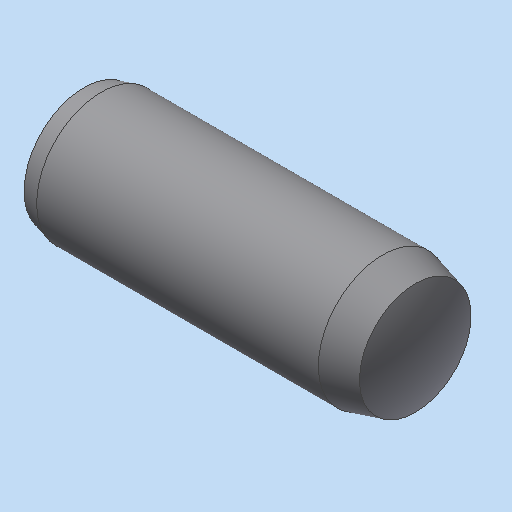
# Autodesk Inventor part: Zylinderstift_DIN_EN_ISO_8735___A6x16
Saved by Autodesk Inventor 2023.3 (Build 273359000, 359)
## iProperties
Shininess: 64.0
Length Units: 11269
Angle Units: 11279
Time Units: 11290
Mass Units: 11283
Length Display Precision: 3
Angle Display Precision: 2
Compacted: True
Part Number: Zylinderstift_DIN_EN_ISO_8735___A6x16
Document SubType Name: Modeling
Created: 2004-04-23
Description: =<RBPARTNOTITLE2>
Vendor: NORM8
Designer: C.Fischer
Manufacturer: Standard
Standards Organization: Custom
Material: xStahl_AnP_Dummymaterial
Mass: 2.68998 g
Surface Area: 4.40403 cm^2
Volume: 0.342673 cm^3
Density: 7.85 g/cm^3
Appearance: RGB(178,178,178)
Density: 0.0
Volumn: 0.0
Area: 0.0
PropertySet Name: Model Information
Control State: 0
Master: False
Checked Out: False
CNS_NB: Zylinderstift DIN EN ISO 8735 - A6x16
CNS_NN: DIN EN ISO 8735-A
CNS_NT: Zylinderstift mit Innengewinde, aus gehaertet Stahl und martensitischem nichtrostendem Stahl, (ISO 8735:1997), Deutsche Fassung EN ISO 8735:1997
CNS_NBSYN: Zylinderstift DIN EN ISO 8735 - $NENN.
CNS_LINA: Zylinderstift DIN EN ISO 8735 - A6x16
CNS_NENN: A6x16
CNS_GEW: M4
CNS_D: 6.000
CNS_D1: 4.000
CNS_D2: 3.242
CNS_DA: 4.300
CNS_P: 0.700
CNS_L: 16.000
CNS_B: 6.000
CNS_A2: 0.800
CNS_A1: 0.600
CNS_A3: 2.100
CNS_T2: 10.000
CNS_T1: 1.000
CNS_KT: X
PSOL_IDENT_0: {C:\partsolutions\data\23d-libs\bosch_bamberg\stifte\scherstifte\din_en_iso_8735_a.prj},182 {M=Nenng
PSOL_IDENT_1: ewinde},{VTYP=3D},{NB=Zylinderstift DIN EN ISO 8735 - A6x16},{NN=DIN EN ISO 8735-A},{DATE=26.11.2003
PSOL_IDENT_2: },{GEOMDATE=26.11.2003},{VERSION=v1},{LINEID=10},{LINESUBID=-1},{WBVAR=}  {NB=Zylinderstift DIN EN I
PSOL_IDENT_3: SO 8735 - A6x16},{LINA=Zylinderstift DIN EN ISO 8735 - A6x16},{KT=X},{IDNR=},{NENN=A6x16},{GEW=M4},{
PSOL_IDENT_4: D=6.000},{D1=4.000},{D2=3.242},{DA=4.300},{P=0.700},{L=16.000},{B=6.000},{A2=0.800},{A1=0.600},{A3=2
PSOL_IDENT_5: .100},{T2=10.000},{T1=1.000}
RBPARTNOTITLE2: Zylinderstift mit Innengewinde, gehaertet
RBPARTNOTITLE1: Parallel pins with internal thread, hardened
RBPARTMADEOF: DIN EN ISO 8735 - A6x16 - St
RBDRAWINGMISSINGSPEC: --
AnP_Kategorie: 2
Title: Zylinderstift DIN EN ISO 8735 - A6x16
Author: C.Fischer
Keywords: =<RBPARTMADEOF>
Comments: =<RBSURFACE2>
Revision Number: 01
Autodesk Inventor part; units mm, degrees
sketch "Skizze_4" plane through (0, 0, 0) normal (0, 1, 0) x (-1, 0, 0)
  line L0 (-24, 0) -> (8, 0)
  line L1 (-10.9359, 0) -> (-10, -1.621)
  line L2 (-10, -1.621) -> (-1.3054, -1.621)
  line L3 (-1.3054, -1.621) -> (-1, -2.15)
  line L4 (-1, -2.15) -> (0, -2.15)
  line L5 (0, -2.15) -> (0, -2.7856)
  line L6 (0, -2.7856) -> (-0.8, -3)
  line L7 (-0.8, -3) -> (-13.9, -3)
  line L8 (-13.9, -3) -> (-15.4096, -2.5955)
  arc A0 (-16, 0) -> (-15.4096, -2.5955) centre (-10, 0) ccw
  line L9 (-16, 0) -> (-10.9359, 0)
  constraints: 20 end point, 2 point on circle, 1 centre point
revolve "Revolution1" add sketch "Skizze_4" angle 360 about axis through (24, 0, 0) along (1, 0, 0)
thread "Thread1" size "M4x0.7" class "6H" standard "ANSI Metric M Profile" length 4.6946
ref_plane "IP2_XY" through (0, 0, 0) normal (1, 0, 0) x (0, 0, -1)
ref_plane "IP2_YZ" through (0, 0, 0) normal (0, 0, -1) x (0, 1, 0)
ref_plane "IP1_XY" through (8, 0, 0) normal (1, 0, 0) x (0, 0, -1)
ref_plane "IP1_YZ" through (8, 0, 0) normal (0, 0, -1) x (0, 1, 0)
ref_plane "IP3_XY" through (16, 0, 0) normal (1, 0, 0) x (0, 0, -1)
ref_plane "IP3_YZ" through (16, 0, 0) normal (0, 0, -1) x (0, 1, 0)
